Autodesk Inventor part; units mm, degrees
(part 3 of 3)
  spline S569 degree 2 poles (13.6657, -5.7927) (13.7991, -5.8668) (14.0609, -6.0817) (14.1868, -6.2002) knots 0 0 0 1 2 2 2
  spline S570 degree 2 poles (14.1868, -6.2002) (14.3968, -6.3929) (14.8463, -6.8646) (14.9773, -7.0054) knots 0 0 0 1 2 2 2
  line L439 (14.9773, -7.0054) -> (14.9773, -5.5086)
  line L440 (14.9773, -5.5086) -> (15.3305, -5.5086)
  spline S571 degree 2 poles (13.8065, -3.2041) (14.6265, -3.2041) (15.3947, -3.6808) (15.3947, -4.1773) knots 0 0 0 1 2 2 2
  spline S572 degree 2 poles (15.3947, -4.1773) (15.3947, -4.6812) (14.6117, -5.1529) (13.8089, -5.1529) knots 0 0 0 1 2 2 2
  spline S573 degree 2 poles (13.8089, -5.1529) (12.9839, -5.1529) (12.2207, -4.6762) (12.2207, -4.1773) knots 0 0 0 1 2 2 2
  spline S574 degree 2 poles (12.2207, -4.1773) (12.2207, -3.6759) (13.0111, -3.2041) (13.8065, -3.2041) knots 0 0 0 1 2 2 2
  spline S575 degree 2 poles (14.7352, -3.7277) (14.5845, -3.6684) (14.1202, -3.619) (13.8065, -3.619) knots 0 0 0 1 2 2 2
  spline S576 degree 2 poles (13.8065, -3.619) (13.4928, -3.619) (13.0309, -3.6684) (12.8753, -3.7302) knots 0 0 0 1 2 2 2
  spline S577 degree 2 poles (12.8753, -3.7302) (12.7197, -3.7919) (12.5591, -4.0068) (12.5591, -4.1773) knots 0 0 0 1 2 2 2
  spline S578 degree 2 poles (12.5591, -4.1773) (12.5591, -4.3477) (12.7197, -4.5675) (12.8802, -4.6318) knots 0 0 0 1 2 2 2
  spline S579 degree 2 poles (12.8802, -4.6318) (13.0358, -4.6935) (13.5101, -4.738) (13.8089, -4.738) knots 0 0 0 1 2 2 2
  spline S580 degree 2 poles (13.8089, -4.738) (14.13, -4.738) (14.5598, -4.6984) (14.7278, -4.6342) knots 0 0 0 1 2 2 2
  spline S581 degree 2 poles (14.7278, -4.6342) (14.8859, -4.5749) (15.0563, -4.3551) (15.0563, -4.1773) knots 0 0 0 1 2 2 2
  spline S582 degree 2 poles (15.0563, -4.1773) (15.0563, -4.0093) (14.8957, -3.7895) (14.7352, -3.7277) knots 0 0 0 1 2 2 2
  line L441 (15.3305, -0.9341) -> (15.3305, -2.8138)
  line L442 (15.3305, -2.8138) -> (14.8982, -2.8138)
  spline S583 degree 2 poles (14.8982, -2.8138) (14.708, -2.6113) (14.3548, -2.2507) (14.1646, -2.0778) knots 0 0 0 1 2 2 2
  spline S584 degree 2 poles (14.1646, -2.0778) (13.7818, -1.7295) (13.3223, -1.4751) (13.0778, -1.4751) knots 0 0 0 1 2 2 2
  spline S585 degree 2 poles (13.0778, -1.4751) (12.9494, -1.4751) (12.7567, -1.5541) (12.695, -1.6257) knots 0 0 0 1 2 2 2
  spline S586 degree 2 poles (12.695, -1.6257) (12.6332, -1.6974) (12.5715, -1.8851) (12.5715, -1.9987) knots 0 0 0 1 2 2 2
  spline S587 degree 2 poles (12.5715, -1.9987) (12.5715, -2.1074) (12.6258, -2.3297) (12.6678, -2.431) knots 0 0 0 1 2 2 2
  spline S588 degree 2 poles (12.6678, -2.431) (12.7024, -2.5174) (12.8012, -2.678) (12.8357, -2.7274) knots 0 0 0 1 2 2 2
  line L443 (12.8357, -2.7274) -> (12.8357, -2.7496)
  line L444 (12.8357, -2.7496) -> (12.401, -2.7496)
  spline S589 degree 2 poles (12.401, -2.7496) (12.3393, -2.6236) (12.2182, -2.1716) (12.2182, -1.9691) knots 0 0 0 1 2 2 2
  spline S590 degree 2 poles (12.2182, -1.9691) (12.2182, -1.5418) (12.6703, -1.0601) (13.0556, -1.0601) knots 0 0 0 1 2 2 2
  spline S591 degree 2 poles (13.0556, -1.0601) (13.2359, -1.0601) (13.5372, -1.1441) (13.6657, -1.2182) knots 0 0 0 1 2 2 2
  spline S592 degree 2 poles (13.6657, -1.2182) (13.7991, -1.2923) (14.0609, -1.5072) (14.1868, -1.6257) knots 0 0 0 1 2 2 2
  spline S593 degree 2 poles (14.1868, -1.6257) (14.3968, -1.8184) (14.8463, -2.2902) (14.9773, -2.431) knots 0 0 0 1 2 2 2
  line L445 (14.9773, -2.431) -> (14.9773, -0.9341)
  line L446 (14.9773, -0.9341) -> (15.3305, -0.9341)
  spline S594 degree 2 poles (12.5715, 0.2959) (12.5715, 0.1848) (12.6258, -0.0351) (12.6678, -0.1413) knots 0 0 0 1 2 2 2
  spline S595 degree 2 poles (12.6678, -0.1413) (12.7098, -0.2401) (12.7987, -0.3858) (12.8382, -0.4426) knots 0 0 0 1 2 2 2
  line L447 (12.8382, -0.4426) -> (12.8382, -0.4673)
  line L448 (12.8382, -0.4673) -> (12.406, -0.4673)
  spline S596 degree 2 poles (12.406, -0.4673) (12.3343, -0.3339) (12.2182, 0.123) (12.2182, 0.328) knots 0 0 0 1 2 2 2
  spline S597 degree 2 poles (12.2182, 0.328) (12.2182, 0.5355) (12.3022, 0.8443) (12.3911, 0.9702) knots 0 0 0 1 2 2 2
  spline S598 degree 2 poles (12.3911, 0.9702) (12.4875, 1.1036) (12.7666, 1.2419) (12.9543, 1.2419) knots 0 0 0 1 2 2 2
  spline S599 degree 2 poles (12.9543, 1.2419) (13.2063, 1.2419) (13.5866, 0.911) (13.636, 0.6788) knots 0 0 0 1 2 2 2
  line L449 (13.636, 0.6788) -> (13.6657, 0.6788)
  spline S600 degree 2 poles (13.6657, 0.6788) (13.6854, 0.7751) (13.7744, 0.9949) (13.8633, 1.0888) knots 0 0 0 1 2 2 2
  spline S601 degree 2 poles (13.8633, 1.0888) (13.9497, 1.1827) (14.2264, 1.3012) (14.4264, 1.3012) knots 0 0 0 1 2 2 2
  spline S602 degree 2 poles (14.4264, 1.3012) (14.6315, 1.3012) (14.9797, 1.1604) (15.1131, 1.032) knots 0 0 0 1 2 2 2
  spline S603 degree 2 poles (15.1131, 1.032) (15.2514, 0.8986) (15.3947, 0.5207) (15.3947, 0.2811) knots 0 0 0 1 2 2 2
  spline S604 degree 2 poles (15.3947, 0.2811) (15.3947, 0.0514) (15.2835, -0.3981) (15.207, -0.5513) knots 0 0 0 1 2 2 2
  line L450 (15.207, -0.5513) -> (14.7747, -0.5513)
  line L451 (14.7747, -0.5513) -> (14.7747, -0.5216)
  spline S605 degree 2 poles (14.7747, -0.5216) (14.8686, -0.3932) (15.0415, 0.0415) (15.0415, 0.2564) knots 0 0 0 1 2 2 2
  spline S606 degree 2 poles (15.0415, 0.2564) (15.0415, 0.3824) (14.9624, 0.6343) (14.871, 0.7183) knots 0 0 0 1 2 2 2
  spline S607 degree 2 poles (14.871, 0.7183) (14.7797, 0.7998) (14.5623, 0.8863) (14.3968, 0.8863) knots 0 0 0 1 2 2 2
  spline S608 degree 2 poles (14.3968, 0.8863) (14.2313, 0.8863) (14.0164, 0.7899) (13.9547, 0.7035) knots 0 0 0 1 2 2 2
  spline S609 degree 2 poles (13.9547, 0.7035) (13.8929, 0.617) (13.846, 0.3824) (13.846, 0.2441) knots 0 0 0 1 2 2 2
  line L452 (13.846, 0.2441) -> (13.846, 0.0712)
  line L453 (13.846, 0.0712) -> (13.5076, 0.0712)
  line L454 (13.5076, 0.0712) -> (13.5076, 0.207)
  spline S610 degree 2 poles (13.5076, 0.207) (13.5076, 0.4812) (13.2458, 0.827) (12.9963, 0.827) knots 0 0 0 1 2 2 2
  spline S611 degree 2 poles (12.9963, 0.827) (12.8802, 0.827) (12.7147, 0.7381) (12.6653, 0.6664) knots 0 0 0 1 2 2 2
  spline S612 degree 2 poles (12.6653, 0.6664) (12.6134, 0.5899) (12.5715, 0.4021) (12.5715, 0.2959) knots 0 0 0 1 2 2 2
  spline S613 degree 2 poles (12.5715, 2.5832) (12.5715, 2.472) (12.6258, 2.2522) (12.6678, 2.146) knots 0 0 0 1 2 2 2
  spline S614 degree 2 poles (12.6678, 2.146) (12.7098, 2.0472) (12.7987, 1.9014) (12.8382, 1.8446) knots 0 0 0 1 2 2 2
  line L455 (12.8382, 1.8446) -> (12.8382, 1.8199)
  line L456 (12.8382, 1.8199) -> (12.406, 1.8199)
  spline S615 degree 2 poles (12.406, 1.8199) (12.3343, 1.9533) (12.2182, 2.4103) (12.2182, 2.6153) knots 0 0 0 1 2 2 2
  spline S616 degree 2 poles (12.2182, 2.6153) (12.2182, 2.8228) (12.3022, 3.1315) (12.3911, 3.2575) knots 0 0 0 1 2 2 2
  spline S617 degree 2 poles (12.3911, 3.2575) (12.4875, 3.3909) (12.7666, 3.5292) (12.9543, 3.5292) knots 0 0 0 1 2 2 2
  spline S618 degree 2 poles (12.9543, 3.5292) (13.2063, 3.5292) (13.5866, 3.1982) (13.636, 2.966) knots 0 0 0 1 2 2 2
  line L457 (13.636, 2.966) -> (13.6657, 2.966)
  spline S619 degree 2 poles (13.6657, 2.966) (13.6854, 3.0623) (13.7744, 3.2822) (13.8633, 3.376) knots 0 0 0 1 2 2 2
  spline S620 degree 2 poles (13.8633, 3.376) (13.9497, 3.4699) (14.2264, 3.5885) (14.4264, 3.5885) knots 0 0 0 1 2 2 2
  spline S621 degree 2 poles (14.4264, 3.5885) (14.6315, 3.5885) (14.9797, 3.4477) (15.1131, 3.3192) knots 0 0 0 1 2 2 2
  spline S622 degree 2 poles (15.1131, 3.3192) (15.2514, 3.1858) (15.3947, 2.8079) (15.3947, 2.5683) knots 0 0 0 1 2 2 2
  spline S623 degree 2 poles (15.3947, 2.5683) (15.3947, 2.3386) (15.2835, 1.8891) (15.207, 1.7359) knots 0 0 0 1 2 2 2
  line L458 (15.207, 1.7359) -> (14.7747, 1.7359)
  line L459 (14.7747, 1.7359) -> (14.7747, 1.7656)
  spline S624 degree 2 poles (14.7747, 1.7656) (14.8686, 1.894) (15.0415, 2.3288) (15.0415, 2.5436) knots 0 0 0 1 2 2 2
  spline S625 degree 2 poles (15.0415, 2.5436) (15.0415, 2.6696) (14.9624, 2.9216) (14.871, 3.0055) knots 0 0 0 1 2 2 2
  spline S626 degree 2 poles (14.871, 3.0055) (14.7797, 3.087) (14.5623, 3.1735) (14.3968, 3.1735) knots 0 0 0 1 2 2 2
  spline S627 degree 2 poles (14.3968, 3.1735) (14.2313, 3.1735) (14.0164, 3.0772) (13.9547, 2.9907) knots 0 0 0 1 2 2 2
  spline S628 degree 2 poles (13.9547, 2.9907) (13.8929, 2.9043) (13.846, 2.6696) (13.846, 2.5313) knots 0 0 0 1 2 2 2
  line L460 (13.846, 2.5313) -> (13.846, 2.3584)
  line L461 (13.846, 2.3584) -> (13.5076, 2.3584)
  line L462 (13.5076, 2.3584) -> (13.5076, 2.4942)
  spline S629 degree 2 poles (13.5076, 2.4942) (13.5076, 2.7684) (13.2458, 3.1142) (12.9963, 3.1142) knots 0 0 0 1 2 2 2
  spline S630 degree 2 poles (12.9963, 3.1142) (12.8802, 3.1142) (12.7147, 3.0253) (12.6653, 2.9537) knots 0 0 0 1 2 2 2
  spline S631 degree 2 poles (12.6653, 2.9537) (12.6134, 2.8771) (12.5715, 2.6894) (12.5715, 2.5832) knots 0 0 0 1 2 2 2
  line L463 (15.3305, 5.7744) -> (15.3305, 4.2875)
  line L464 (15.3305, 4.2875) -> (15.0192, 4.2875)
  line L465 (15.0192, 4.2875) -> (15.0192, 4.8408)
  line L466 (15.0192, 4.8408) -> (12.9765, 4.8408)
  line L467 (12.9765, 4.8408) -> (12.9765, 4.2875)
  line L468 (12.9765, 4.2875) -> (12.6974, 4.2875)
  spline S632 degree 2 poles (12.6974, 4.2875) (12.6974, 4.6012) (12.5196, 4.8976) (12.2726, 4.9173) knots 0 0 0 1 2 2 2
  line L469 (12.2726, 4.9173) -> (12.2726, 5.2335)
  line L470 (12.2726, 5.2335) -> (15.0192, 5.2335)
  line L471 (15.0192, 5.2335) -> (15.0192, 5.7744)
  line L472 (15.0192, 5.7744) -> (15.3305, 5.7744)
  spline S633 degree 2 poles (12.5715, 7.1576) (12.5715, 7.0465) (12.6258, 6.8267) (12.6678, 6.7204) knots 0 0 0 1 2 2 2
  spline S634 degree 2 poles (12.6678, 6.7204) (12.7098, 6.6216) (12.7987, 6.4759) (12.8382, 6.4191) knots 0 0 0 1 2 2 2
  line L473 (12.8382, 6.4191) -> (12.8382, 6.3944)
  line L474 (12.8382, 6.3944) -> (12.406, 6.3944)
  spline S635 degree 2 poles (12.406, 6.3944) (12.3343, 6.5278) (12.2182, 6.9847) (12.2182, 7.1897) knots 0 0 0 1 2 2 2
  spline S636 degree 2 poles (12.2182, 7.1897) (12.2182, 7.3972) (12.3022, 7.706) (12.3911, 7.8319) knots 0 0 0 1 2 2 2
  spline S637 degree 2 poles (12.3911, 7.8319) (12.4875, 7.9653) (12.7666, 8.1037) (12.9543, 8.1037) knots 0 0 0 1 2 2 2
  spline S638 degree 2 poles (12.9543, 8.1037) (13.2063, 8.1037) (13.5866, 7.7727) (13.636, 7.5405) knots 0 0 0 1 2 2 2
  line L475 (13.636, 7.5405) -> (13.6657, 7.5405)
  spline S639 degree 2 poles (13.6657, 7.5405) (13.6854, 7.6368) (13.7744, 7.8566) (13.8633, 7.9505) knots 0 0 0 1 2 2 2
  spline S640 degree 2 poles (13.8633, 7.9505) (13.9497, 8.0444) (14.2264, 8.1629) (14.4264, 8.1629) knots 0 0 0 1 2 2 2
  spline S641 degree 2 poles (14.4264, 8.1629) (14.6315, 8.1629) (14.9797, 8.0221) (15.1131, 7.8937) knots 0 0 0 1 2 2 2
  spline S642 degree 2 poles (15.1131, 7.8937) (15.2514, 7.7603) (15.3947, 7.3824) (15.3947, 7.1428) knots 0 0 0 1 2 2 2
  spline S643 degree 2 poles (15.3947, 7.1428) (15.3947, 6.9131) (15.2835, 6.4636) (15.207, 6.3104) knots 0 0 0 1 2 2 2
  line L476 (15.207, 6.3104) -> (14.7747, 6.3104)
  line L477 (14.7747, 6.3104) -> (14.7747, 6.3401)
  spline S644 degree 2 poles (14.7747, 6.3401) (14.8686, 6.4685) (15.0415, 6.9032) (15.0415, 7.1181) knots 0 0 0 1 2 2 2
  spline S645 degree 2 poles (15.0415, 7.1181) (15.0415, 7.2441) (14.9624, 7.496) (14.871, 7.58) knots 0 0 0 1 2 2 2
  spline S646 degree 2 poles (14.871, 7.58) (14.7797, 7.6615) (14.5623, 7.748) (14.3968, 7.748) knots 0 0 0 1 2 2 2
  spline S647 degree 2 poles (14.3968, 7.748) (14.2313, 7.748) (14.0164, 7.6516) (13.9547, 7.5652) knots 0 0 0 1 2 2 2
  spline S648 degree 2 poles (13.9547, 7.5652) (13.8929, 7.4787) (13.846, 7.2441) (13.846, 7.1058) knots 0 0 0 1 2 2 2
  line L478 (13.846, 7.1058) -> (13.846, 6.9329)
  line L479 (13.846, 6.9329) -> (13.5076, 6.9329)
  line L480 (13.5076, 6.9329) -> (13.5076, 7.0687)
  spline S649 degree 2 poles (13.5076, 7.0687) (13.5076, 7.3429) (13.2458, 7.6887) (12.9963, 7.6887) knots 0 0 0 1 2 2 2
  spline S650 degree 2 poles (12.9963, 7.6887) (12.8802, 7.6887) (12.7147, 7.5998) (12.6653, 7.5281) knots 0 0 0 1 2 2 2
  spline S651 degree 2 poles (12.6653, 7.5281) (12.6134, 7.4516) (12.5715, 7.2638) (12.5715, 7.1576) knots 0 0 0 1 2 2 2
  spline S652 degree 2 poles (13.8065, 10.5193) (14.6265, 10.5193) (15.3947, 10.0426) (15.3947, 9.5461) knots 0 0 0 1 2 2 2
  spline S653 degree 2 poles (15.3947, 9.5461) (15.3947, 9.0423) (14.6117, 8.5705) (13.8089, 8.5705) knots 0 0 0 1 2 2 2
  spline S654 degree 2 poles (13.8089, 8.5705) (12.9839, 8.5705) (12.2207, 9.0472) (12.2207, 9.5461) knots 0 0 0 1 2 2 2
  spline S655 degree 2 poles (12.2207, 9.5461) (12.2207, 10.0476) (13.0111, 10.5193) (13.8065, 10.5193) knots 0 0 0 1 2 2 2
  spline S656 degree 2 poles (14.7352, 9.9957) (14.5845, 10.055) (14.1202, 10.1044) (13.8065, 10.1044) knots 0 0 0 1 2 2 2
  spline S657 degree 2 poles (13.8065, 10.1044) (13.4928, 10.1044) (13.0309, 10.055) (12.8753, 9.9932) knots 0 0 0 1 2 2 2
  spline S658 degree 2 poles (12.8753, 9.9932) (12.7197, 9.9315) (12.5591, 9.7166) (12.5591, 9.5461) knots 0 0 0 1 2 2 2
  spline S659 degree 2 poles (12.5591, 9.5461) (12.5591, 9.3757) (12.7197, 9.1559) (12.8802, 9.0917) knots 0 0 0 1 2 2 2
  spline S660 degree 2 poles (12.8802, 9.0917) (13.0358, 9.0299) (13.5101, 8.9854) (13.8089, 8.9854) knots 0 0 0 1 2 2 2
  spline S661 degree 2 poles (13.8089, 8.9854) (14.13, 8.9854) (14.5598, 9.025) (14.7278, 9.0892) knots 0 0 0 1 2 2 2
  spline S662 degree 2 poles (14.7278, 9.0892) (14.8859, 9.1485) (15.0563, 9.3683) (15.0563, 9.5461) knots 0 0 0 1 2 2 2
  spline S663 degree 2 poles (15.0563, 9.5461) (15.0563, 9.7141) (14.8957, 9.9339) (14.7352, 9.9957) knots 0 0 0 1 2 2 2
  spline S664 degree 2 poles (15.3996, 11.8309) (15.3996, 11.6037) (15.2638, 11.2307) (15.1378, 11.0998) knots 0 0 0 1 2 2 2
  spline S665 degree 2 poles (15.1378, 11.0998) (15.0143, 10.9713) (14.6784, 10.838) (14.4882, 10.838) knots 0 0 0 1 2 2 2
  spline S666 degree 2 poles (14.4882, 10.838) (14.2412, 10.838) (13.8262, 11.1023) (13.7027, 11.3542) knots 0 0 0 1 2 2 2
  line L481 (13.7027, 11.3542) -> (13.6904, 11.3542)
  spline S667 degree 2 poles (13.6904, 11.3542) (13.5595, 11.1294) (13.2482, 10.9121) (13.0161, 10.9121) knots 0 0 0 1 2 2 2
  spline S668 degree 2 poles (13.0161, 10.9121) (12.6727, 10.9121) (12.2133, 11.4308) (12.2133, 11.8309) knots 0 0 0 1 2 2 2
  spline S669 degree 2 poles (12.2133, 11.8309) (12.2133, 12.2459) (12.648, 12.7473) (12.9889, 12.7473) knots 0 0 0 1 2 2 2
  spline S670 degree 2 poles (12.9889, 12.7473) (13.1939, 12.7473) (13.594, 12.5077) (13.7077, 12.2829) knots 0 0 0 1 2 2 2
  line L482 (13.7077, 12.2829) -> (13.72, 12.2829)
  spline S671 degree 2 poles (13.72, 12.2829) (13.8435, 12.5497) (14.1992, 12.8239) (14.4808, 12.8239) knots 0 0 0 1 2 2 2
  spline S672 degree 2 poles (14.4808, 12.8239) (14.871, 12.8239) (15.3996, 12.2557) (15.3996, 11.8309) knots 0 0 0 1 2 2 2
  spline S673 degree 2 poles (14.5203, 12.4039) (14.3326, 12.4039) (14.1103, 12.2557) (13.9967, 12.0458) knots 0 0 0 1 2 2 2
  spline S674 degree 2 poles (13.9967, 12.0458) (13.9571, 11.9766) (13.8657, 11.7445) (13.8065, 11.5987) knots 0 0 0 1 2 2 2
  spline S675 degree 2 poles (13.8065, 11.5987) (13.9176, 11.4308) (14.2486, 11.2505) (14.4585, 11.2505) knots 0 0 0 1 2 2 2
  spline S676 degree 2 poles (14.4585, 11.2505) (14.7352, 11.2505) (15.0958, 11.5839) (15.0958, 11.8358) knots 0 0 0 1 2 2 2
  spline S677 degree 2 poles (15.0958, 11.8358) (15.0958, 12.0927) (14.7871, 12.4039) (14.5203, 12.4039) knots 0 0 0 1 2 2 2
  spline S678 degree 2 poles (12.9938, 12.3471) (12.7888, 12.3471) (12.5146, 12.073) (12.5146, 11.8284) knots 0 0 0 1 2 2 2
  spline S679 degree 2 poles (12.5146, 11.8284) (12.5146, 11.6061) (12.7592, 11.3221) (12.9691, 11.3221) knots 0 0 0 1 2 2 2
  spline S680 degree 2 poles (12.9691, 11.3221) (13.1198, 11.3221) (13.3298, 11.4678) (13.4137, 11.6135) knots 0 0 0 1 2 2 2
  spline S681 degree 2 poles (13.4137, 11.6135) (13.4483, 11.6753) (13.5693, 11.9371) (13.6039, 12.0433) knots 0 0 0 1 2 2 2
  spline S682 degree 2 poles (13.6039, 12.0433) (13.4681, 12.2212) (13.1791, 12.3471) (12.9938, 12.3471) knots 0 0 0 1 2 2 2
  dimension "d4" = 75
  dimension "d5" = 161.83
  constraints: 4 other
extrude "Extrusion11" add sketch "Sketch21" along normal blind 1
body "Solid1"
